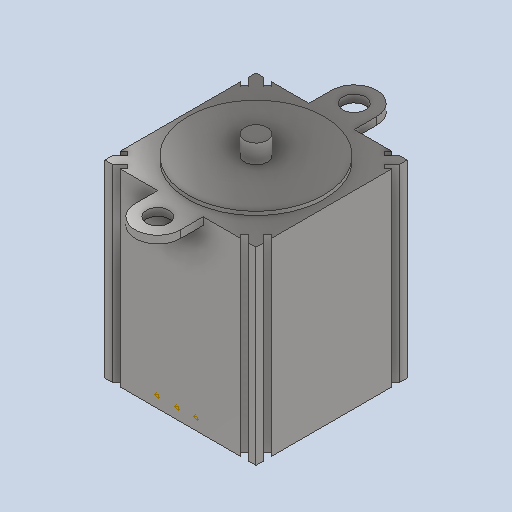
# Autodesk Inventor part: servo_motor
Saved by Autodesk Inventor 2026.1 (Build 301233020, 233B)
## iProperties
Created: 2025-11-26
Part Number: servo_motor
Material: Acciaio, Carbonio
Document SubType Name: Modeling
Designer: maxbu
Density: 7.85 g/cm^3
Appearance: Semilucidato
Mass: 78.8536 g
Surface Area: 33.435 cm^2
Volume: 10.045 cm^3
Categories: <MemberInstance><Categories><Category DisplayName="" Mnemonic="CABLEANDHARNESS" InternalName="e4a7e005-5e42-4d16-b293-125e7f0d0512"><Category DisplayName="" Mnemonic="CONNECTORS" InternalName="6f634eba-a678-4820-a31d-2c2d5ee6728e"><CategoryParameter DisplayName="" Mnemonic="REFDES" InternalName="c3740e8c-60ab-4d5d-8584-52b73222f2f0"/><Category DisplayName="" Mnemonic="DISCRETEWIRE" InternalName="9a3407de-09b2-4cdb-8c40-9708d5144a28"/></Category></Category></Categories><FamilyTemplate><FamilyTemplateParameters></FamilyTemplateParameters></FamilyTemplate><CategoryParameterMap><ParamToTemplateMap><ParamToTemplate CategoryParameter="//CategoryParameter[@InternalName='c3740e8c-60ab-4d5d-8584-52b73222f2f0']" ConstantValue=""/></ParamToTemplateMap></CategoryParameterMap></MemberInstance>
Author: maxbu
Autodesk Inventor part; units mm, degrees
ref_plane "YZ Plane" through (0, 0, 0) normal (1, 0, 0) x (0, 1, 0)
ref_plane "XZ Plane" through (0, 0, 0) normal (0, 1, 0) x (-1, 0, 0)
ref_plane "XY Plane" through (0, 0, 0) normal (0, 0, 1) x (1, 0, 0)
sketch "Schizzo5" plane through (0, 0, 0) normal (0, 1, 0) x (-1, 0, 0)
  line L0 (-10, 10) -> (10, 10)
  line L1 (10, 10) -> (10, -10)
  line L2 (10, -10) -> (-10, -10)
  line L3 (-10, -10) -> (-10, 10)
  line L4 (-10, 10) -> (10, -10) construction
  line L5 (10, 10) -> (-10, -10) construction
  line L6 (10, 9) -> (9, 8)
  line L7 (9, 8) -> (9.5, 7.5)
  line L8 (9.5, 7.5) -> (10, 8)
  line L9 (9, 10) -> (8, 9)
  line L10 (8, 9) -> (7.5, 9.5)
  line L11 (7.5, 9.5) -> (8, 10)
  line L12 (-9, -10) -> (-8, -9)
  line L13 (-8, -9) -> (-7.5, -9.5)
  line L14 (-7.5, -9.5) -> (-8, -10)
  line L15 (-10, -9) -> (-9, -8)
  line L16 (-9, -8) -> (-9.5, -7.5)
  line L17 (-9.5, -7.5) -> (-10, -8)
  line L18 (-10, 0) -> (10, 0) construction
  line L19 (10, -9) -> (9, -8)
  line L20 (9, -8) -> (9.5, -7.5)
  line L21 (9.5, -7.5) -> (10, -8)
  line L22 (9, -10) -> (8, -9)
  line L23 (8, -9) -> (7.5, -9.5)
  line L24 (7.5, -9.5) -> (8, -10)
  line L25 (-9, 8) -> (-9.5, 7.5)
  line L26 (-9.5, 7.5) -> (-10, 8)
  line L27 (-10, 9) -> (-9, 8)
  line L28 (-9, 10) -> (-8, 9)
  line L29 (-8, 9) -> (-7.5, 9.5)
  line L30 (-7.5, 9.5) -> (-8, 10)
  point P0 (0, 0)
  dimension "d29" = 20
  dimension "d30" = 1
  dimension "d31" = 1
  constraints: 62 end point, 28 symmetric about line, 5 perpendicular, 4 midpoint, 3 parallel, 2 point on line, 1 horizontal
  measures "d29" distance of L0.end L1.end
  measures "d30" horizontal distance of L9.start L9.end
  measures "d31" distance of L0.end L6.start
extrude "Estrusione4" add sketch "Schizzo5" along normal blind 25 contours L0 L28 L29 L30 L11 L10 L9 L1 L6 L7 L8 L21 L20 L19 L2 L22 L23 L24 L14 L13 L12 L3 L15 L16 L17 L26 L25 L27
sketch "Schizzo7" plane through (0, 25, 0) normal (0, 1, 0) x (1, 0, 0)
  line L0 (0, 0) -> (0, 13) construction
  circle A0 centre (0, 13) radius 1.5
  arc A1 (3, 13) -> (-3, 13) centre (0, 13) ccw
  line L1 (-3, 13) -> (-3, 10)
  line L2 (8, 10) -> (-8, 10) projected
  line L3 (3, 13) -> (3, 10)
  line L4 (-3, 10) -> (3, 10)
  line L5 (0, 0) -> (10, 0) construction
  line L6 (10, -8) -> (10, 8) projected
  line L7 (0, 0) -> (0, -13) construction
  circle A2 centre (0, -13) radius 1.5
  arc A3 (-3, -13) -> (3, -13) centre (0, -13) ccw
  line L8 (-3, -13) -> (-3, -10)
  line L9 (3, -13) -> (3, -10)
  line L10 (-3, -10) -> (3, -10)
  line L11 (-8, -10) -> (8, -10) projected
  circle A4 centre (0, 13) radius 3 construction
  dimension "d40" = 3
  dimension "d41" = 3
  dimension "d50" = 3
  constraints: 18 end point, 7 symmetric about line, 5 coincident, 4 centre point, 4 point on circle, 2 collinear, 2 point on line, 2 tangent, 2 vertical, 1 horizontal alignment, 1 midpoint, 1 perpendicular, 4 other
  measures "d40" diameter of A0
  measures "d41" radius of A1
  measures "d50" distance from line of L2 A0.centre
extrude "Estrusione6" add sketch "Schizzo7" against normal blind 1
sketch "Schizzo8" plane through (0, 25, 0) normal (0, 1, 0) x (1, 0, 0)
  circle A0 centre (0, 0) radius 9
  dimension "d44" = 18
  constraints: 1 centre point, 1 coincident
  measures "d44" diameter of A0
extrude "Estrusione7" add sketch "Schizzo8" along normal blind 0.5
sketch "Schizzo9" plane through (0, 25.5, 0) normal (0, 1, 0) x (1, 0, 0)
  circle A0 centre (0, 0) radius 1.5
  dimension "d47" = 3
  constraints: 1 centre point, 1 coincident
  measures "d47" diameter of A0
extrude "Estrusione8" add sketch "Schizzo9" along normal blind 2.5
